Autodesk Fusion 360 part; units mm, degrees
(part 3 of 8)
  spline S51 degree 5 poles (4.880225, -3.252666) (4.880415, -3.252751) (4.882389, -3.253634) (4.886153, -3.255305) (4.891721, -3.257742) (4.899117, -3.260906) (4.908178, -3.264669) (4.917292, -3.268345) (4.926453, -3.271945) (4.935655, -3.275478) (4.944894, -3.278951) (4.954168, -3.282368) (4.963475, -3.28573) (4.972817, -3.289036) (4.982195, -3.292282) (4.991608, -3.295469) (5.001056, -3.298597) (5.010539, -3.301666) (5.020055, -3.30468) (5.029603, -3.30764) (5.03918, -3.310549) (5.048788, -3.313407) (5.058424, -3.316215) (5.068089, -3.318973) (5.077782, -3.321682) (5.087504, -3.324341) (5.097254, -3.326951) (5.107031, -3.329512) (5.116835, -3.332026) (5.126666, -3.334492) (5.136522, -3.336912) (5.146404, -3.339287) (5.156311, -3.341616) (5.166242, -3.3439) (5.176198, -3.346139) (5.186178, -3.348333) (5.196182, -3.350483) (5.20621, -3.35259) (5.216261, -3.354653) (5.226335, -3.356672) (5.236431, -3.358649) (5.24655, -3.360583) (5.256691, -3.362476) (5.266853, -3.364326) (5.277038, -3.366134) (5.287243, -3.367901) (5.29747, -3.369627) (5.307717, -3.371311) (5.317985, -3.372955) (5.328274, -3.374558) (5.338583, -3.376121) (5.348911, -3.377644) (5.35926, -3.379126) (5.369627, -3.380569) (5.380015, -3.381972) (5.390421, -3.383336) (5.400847, -3.38466) (5.411291, -3.385946) (5.421753, -3.387192) (5.432234, -3.3884) (5.442733, -3.389569) (5.45325, -3.390699) (5.463785, -3.391792) (5.472228, -3.392635) (5.478567, -3.39325) (5.482797, -3.393652) (5.484913, -3.393852) knots 0.1270499 0.1270499 0.1270499 0.1270499 0.1270499 0.1270499 0.12857143 0.14285714 0.15714286 0.17142857 0.18571429 0.2 0.21428571 0.22857143 0.24285714 0.25714286 0.27142857 0.28571429 0.3 0.31428571 0.32857143 0.34285714 0.35714286 0.37142857 0.38571429 0.4 0.41428571 0.42857143 0.44285714 0.45714286 0.47142857 0.48571429 0.5 0.51428571 0.52857143 0.54285714 0.55714286 0.57142857 0.58571429 0.6 0.61428571 0.62857143 0.64285714 0.65714286 0.67142857 0.68571429 0.7 0.71428571 0.72857143 0.74285714 0.75714286 0.77142857 0.78571429 0.8 0.81428571 0.82857143 0.84285714 0.85714286 0.87142857 0.88571429 0.9 0.91428571 0.92857143 0.94285714 0.95714286 0.97142857 0.98571429 1 1 1 1 1 1
  arc A17 (5.484913, -3.393852) -> (5.601792, -3.197253) centre (0, 0) ccw
  spline S52 degree 5 poles (5.601792, -3.197253) (5.600606, -3.19549) (5.598232, -3.191966) (5.594663, -3.18669) (5.589889, -3.179676) (5.583897, -3.170943) (5.577879, -3.162244) (5.571837, -3.153579) (5.565769, -3.144948) (5.559676, -3.136352) (5.553557, -3.127791) (5.547413, -3.119264) (5.541244, -3.110774) (5.535049, -3.102319) (5.528828, -3.0939) (5.522582, -3.085517) (5.51631, -3.07717) (5.510013, -3.068861) (5.503689, -3.060588) (5.49734, -3.052352) (5.490965, -3.044155) (5.484563, -3.035995) (5.478136, -3.027873) (5.471682, -3.01979) (5.465201, -3.011746) (5.458695, -3.003741) (5.452161, -2.995776) (5.445601, -2.98785) (5.439015, -2.979965) (5.432401, -2.972121) (5.42576, -2.964318) (5.419092, -2.956556) (5.412396, -2.948837) (5.405673, -2.94116) (5.398922, -2.933526) (5.392144, -2.925935) (5.385337, -2.918388) (5.378502, -2.910886) (5.371639, -2.903428) (5.364747, -2.896016) (5.357826, -2.88865) (5.350876, -2.881331) (5.343895, -2.874061) (5.336885, -2.866839) (5.329845, -2.859666) (5.322774, -2.852542) (5.315674, -2.845467) (5.308543, -2.838442) (5.301382, -2.831469) (5.294188, -2.824549) (5.286961, -2.817684) (5.2797, -2.810878) (5.272403, -2.804131) (5.265071, -2.797443) (5.257705, -2.790815) (5.250305, -2.784245) (5.242872, -2.77773) (5.235408, -2.771273) (5.227908, -2.764876) (5.220369, -2.758548) (5.212786, -2.752298) (5.205152, -2.746135) (5.198838, -2.741149) (5.194037, -2.737422) (5.190771, -2.734913) (5.189053, -2.7336) (5.188887, -2.733474) knots -1 -1 -1 -1 -1 -1 -0.98571429 -0.97142857 -0.95714286 -0.94285714 -0.92857143 -0.91428571 -0.9 -0.88571429 -0.87142857 -0.85714286 -0.84285714 -0.82857143 -0.81428571 -0.8 -0.78571429 -0.77142857 -0.75714286 -0.74285714 -0.72857143 -0.71428571 -0.7 -0.68571429 -0.67142857 -0.65714286 -0.64285714 -0.62857143 -0.61428571 -0.6 -0.58571429 -0.57142857 -0.55714286 -0.54285714 -0.52857143 -0.51428571 -0.5 -0.48571429 -0.47142857 -0.45714286 -0.44285714 -0.42857143 -0.41428571 -0.4 -0.38571429 -0.37142857 -0.35714286 -0.34285714 -0.32857143 -0.31428571 -0.3 -0.28571429 -0.27142857 -0.25714286 -0.24285714 -0.22857143 -0.21428571 -0.2 -0.18571429 -0.17142857 -0.15714286 -0.14285714 -0.12857143 -0.1270499 -0.1270499 -0.1270499 -0.1270499 -0.1270499 -0.1270499
  spline S53 degree 3 poles (5.319548, -2.469584) (5.300709, -2.464423) (5.281043, -2.462992) (5.242269, -2.467747) (5.223532, -2.473889) (5.189467, -2.49301) (5.174464, -2.505805) (5.150209, -2.536427) (5.141187, -2.55396) (5.130373, -2.591498) (5.128683, -2.611143) (5.13293, -2.649976) (5.138825, -2.668792) (5.153188, -2.695188) (5.159174, -2.703872) (5.172862, -2.719846) (5.180527, -2.727091) (5.188887, -2.733474) knots 0 0 0 0 0.00585967 0.00585967 0.01171933 0.01171933 0.017579 0.017579 0.02343867 0.02343867 0.02929834 0.02929834 0.035158 0.035158 0.03831344 0.03831344 0.04146887 0.04146887 0.04146887 0.04146887
  spline S54 degree 5 poles (5.319548, -2.469584) (5.319748, -2.469639) (5.321834, -2.470209) (5.325809, -2.471286) (5.331684, -2.472845) (5.339477, -2.474843) (5.349006, -2.477178) (5.358574, -2.479421) (5.368177, -2.48158) (5.377811, -2.483666) (5.387472, -2.485688) (5.397158, -2.48765) (5.40687, -2.489552) (5.416607, -2.491392) (5.42637, -2.49317) (5.436159, -2.494882) (5.445975, -2.496531) (5.455815, -2.498117) (5.465679, -2.499643) (5.475567, -2.501111) (5.485476, -2.502523) (5.495407, -2.503881) (5.505359, -2.505186) (5.515332, -2.506436) (5.525325, -2.507633) (5.535339, -2.508777) (5.545373, -2.509868) (5.555427, -2.510907) (5.565499, -2.511894) (5.575591, -2.512832) (5.585702, -2.513719) (5.59583, -2.514557) (5.605976, -2.515346) (5.61614, -2.516087) (5.626321, -2.51678) (5.636519, -2.517426) (5.646734, -2.518024) (5.656966, -2.518575) (5.667214, -2.519079) (5.677478, -2.519537) (5.687758, -2.51995) (5.698053, -2.520317) (5.708364, -2.520639) (5.71869, -2.520916) (5.729031, -2.521149) (5.739387, -2.521337) (5.749757, -2.521481) (5.760141, -2.521582) (5.77054, -2.521639) (5.780953, -2.521653) (5.791379, -2.521623) (5.801819, -2.521552) (5.812272, -2.521437) (5.822739, -2.52128) (5.833219, -2.521081) (5.843712, -2.520841) (5.854217, -2.520558) (5.864735, -2.520234) (5.875265, -2.519869) (5.885808, -2.519462) (5.896362, -2.519015) (5.906928, -2.518527) (5.917507, -2.517998) (5.925979, -2.517543) (5.932338, -2.517183) (5.93658, -2.516935) (5.938701, -2.516809) knots 0.1270499 0.1270499 0.1270499 0.1270499 0.1270499 0.1270499 0.12857143 0.14285714 0.15714286 0.17142857 0.18571429 0.2 0.21428571 0.22857143 0.24285714 0.25714286 0.27142857 0.28571429 0.3 0.31428571 0.32857143 0.34285714 0.35714286 0.37142857 0.38571429 0.4 0.41428571 0.42857143 0.44285714 0.45714286 0.47142857 0.48571429 0.5 0.51428571 0.52857143 0.54285714 0.55714286 0.57142857 0.58571429 0.6 0.61428571 0.62857143 0.64285714 0.65714286 0.67142857 0.68571429 0.7 0.71428571 0.72857143 0.74285714 0.75714286 0.77142857 0.78571429 0.8 0.81428571 0.82857143 0.84285714 0.85714286 0.87142857 0.88571429 0.9 0.91428571 0.92857143 0.94285714 0.95714286 0.97142857 0.98571429 1 1 1 1 1 1
  arc A18 (5.938701, -2.516809) -> (6.0242, -2.304673) centre (0, 0) ccw
  spline S55 degree 5 poles (6.0242, -2.304673) (6.022758, -2.303111) (6.019874, -2.299991) (6.015542, -2.295322) (6.009753, -2.289119) (6.002498, -2.281403) (5.995223, -2.273724) (5.987929, -2.266083) (5.980614, -2.25848) (5.97328, -2.250915) (5.965927, -2.243388) (5.958553, -2.235899) (5.95116, -2.22845) (5.943747, -2.22104) (5.936314, -2.213669) (5.928862, -2.206338) (5.921389, -2.199046) (5.913897, -2.191795) (5.906385, -2.184585) (5.898853, -2.177415) (5.891301, -2.170287) (5.883729, -2.1632) (5.876137, -2.156154) (5.868525, -2.149151) (5.860892, -2.14219) (5.85324, -2.135273) (5.845567, -2.128398) (5.837874, -2.121567) (5.830161, -2.114779) (5.822427, -2.108037) (5.814673, -2.101339) (5.806899, -2.094686) (5.799103, -2.088079) (5.791287, -2.081519) (5.78345, -2.075005) (5.775592, -2.068538) (5.767713, -2.062118) (5.759813, -2.055747) (5.751892, -2.049424) (5.743949, -2.043151) (5.735985, -2.036928) (5.727999, -2.030756) (5.71999, -2.024636) (5.71196, -2.018569) (5.703907, -2.012555) (5.695832, -2.006593) (5.687735, -2.000685) (5.679616, -1.994832) (5.671473, -1.989033) (5.663308, -1.983292) (5.655118, -1.977611) (5.646903, -1.971993) (5.638662, -1.966439) (5.630395, -1.960949) (5.622103, -1.955523) (5.613786, -1.950159) (5.605447, -1.944856) (5.597084, -1.939614) (5.588696, -1.934437) (5.580279, -1.929333) (5.57183, -1.924314) (5.563345, -1.919389) (5.556345, -1.915425) (5.551031, -1.912474) (5.54742, -1.910494) (5.545521, -1.909458) (5.545338, -1.909359) knots -1 -1 -1 -1 -1 -1 -0.98571429 -0.97142857 -0.95714286 -0.94285714 -0.92857143 -0.91428571 -0.9 -0.88571429 -0.87142857 -0.85714286 -0.84285714 -0.82857143 -0.81428571 -0.8 -0.78571429 -0.77142857 -0.75714286 -0.74285714 -0.72857143 -0.71428571 -0.7 -0.68571429 -0.67142857 -0.65714286 -0.64285714 -0.62857143 -0.61428571 -0.6 -0.58571429 -0.57142857 -0.55714286 -0.54285714 -0.52857143 -0.51428571 -0.5 -0.48571429 -0.47142857 -0.45714286 -0.44285714 -0.42857143 -0.41428571 -0.4 -0.38571429 -0.37142857 -0.35714286 -0.34285714 -0.32857143 -0.31428571 -0.3 -0.28571429 -0.27142857 -0.25714286 -0.24285714 -0.22857143 -0.21428571 -0.2 -0.18571429 -0.17142857 -0.15714286 -0.14285714 -0.12857143 -0.1270499 -0.1270499 -0.1270499 -0.1270499 -0.1270499 -0.1270499
  spline S56 degree 3 poles (5.634185, -1.628616) (5.61478, -1.626392) (5.595126, -1.627979) (5.557532, -1.638598) (5.539952, -1.647528) (5.509205, -1.671624) (5.496331, -1.68656) (5.477034, -1.720525) (5.470795, -1.73923) (5.465837, -1.777979) (5.467167, -1.797652) (5.477291, -1.835382) (5.48599, -1.853077) (5.504214, -1.876971) (5.511455, -1.88464) (5.527421, -1.898337) (5.536102, -1.904327) (5.545338, -1.909359) knots 0 0 0 0 0.00585967 0.00585967 0.01171933 0.01171933 0.017579 0.017579 0.02343867 0.02343867 0.02929834 0.02929834 0.035158 0.035158 0.03831344 0.03831344 0.04146887 0.04146887 0.04146887 0.04146887
  spline S57 degree 5 poles (5.634185, -1.628616) (5.634392, -1.62864) (5.63654, -1.628885) (5.640633, -1.629343) (5.646677, -1.629986) (5.654683, -1.630772) (5.664457, -1.631625) (5.674256, -1.63238) (5.684076, -1.633048) (5.693915, -1.63364) (5.703771, -1.634163) (5.713644, -1.634624) (5.723532, -1.635021) (5.733436, -1.635353) (5.743356, -1.635619) (5.753292, -1.635818) (5.763244, -1.635948) (5.773211, -1.636014) (5.783193, -1.636016) (5.793188, -1.635957) (5.803197, -1.635841) (5.813219, -1.635667) (5.823253, -1.635437) (5.8333, -1.63515) (5.843359, -1.634808) (5.85343, -1.63441) (5.863513, -1.633956) (5.873607, -1.633448) (5.883713, -1.632887) (5.89383, -1.632272) (5.903957, -1.631606) (5.914094, -1.630888) (5.924242, -1.630119) (5.9344, -1.6293) (5.944568, -1.628431) (5.954745, -1.627512) (5.964931, -1.626544) (5.975127, -1.625526) (5.985332, -1.62446) (5.995546, -1.623346) (6.005768, -1.622185) (6.015999, -1.620976) (6.026238, -1.61972) (6.036485, -1.618418) (6.046741, -1.617069) (6.057004, -1.615675) (6.067274, -1.614234) (6.077553, -1.612748) (6.087838, -1.611217) (6.098131, -1.609642) (6.108431, -1.608021) (6.118737, -1.606357) (6.129051, -1.604648) (6.139371, -1.602895) (6.149697, -1.601099) (6.16003, -1.599259) (6.170369, -1.597376) (6.180715, -1.595451) (6.191066, -1.593482) (6.201423, -1.591471) (6.211785, -1.589418) (6.222153, -1.587323) (6.232527, -1.585185) (6.24083, -1.583442) (6.24706, -1.582116) (6.251214, -1.581223) (6.253291, -1.580775) knots 0.1270499 0.1270499 0.1270499 0.1270499 0.1270499 0.1270499 0.12857143 0.14285714 0.15714286 0.17142857 0.18571429 0.2 0.21428571 0.22857143 0.24285714 0.25714286 0.27142857 0.28571429 0.3 0.31428571 0.32857143 0.34285714 0.35714286 0.37142857 0.38571429 0.4 0.41428571 0.42857143 0.44285714 0.45714286 0.47142857 0.48571429 0.5 0.51428571 0.52857143 0.54285714 0.55714286 0.57142857 0.58571429 0.6 0.61428571 0.62857143 0.64285714 0.65714286 0.67142857 0.68571429 0.7 0.71428571 0.72857143 0.74285714 0.75714286 0.77142857 0.78571429 0.8 0.81428571 0.82857143 0.84285714 0.85714286 0.87142857 0.88571429 0.9 0.91428571 0.92857143 0.94285714 0.95714286 0.97142857 0.98571429 1 1 1 1 1 1
  arc A19 (6.253291, -1.580775) -> (6.305405, -1.358074) centre (0, 0) ccw
  spline S58 degree 5 poles (6.305405, -1.358074) (6.303743, -1.35675) (6.300416, -1.354107) (6.295421, -1.350154) (6.288754, -1.344907) (6.280406, -1.338389) (6.272044, -1.331911) (6.263669, -1.325473) (6.255279, -1.319075) (6.246877, -1.312718) (6.23846, -1.306402) (6.23003, -1.300127) (6.221586, -1.293893) (6.213129, -1.287701) (6.204658, -1.281551) (6.196174, -1.275444) (6.187676, -1.269379) (6.179165, -1.263356) (6.17064, -1.257377) (6.162102, -1.251441) (6.15355, -1.245549) (6.144985, -1.239701) (6.136406, -1.233897) (6.127814, -1.228138) (6.119209, -1.222424) (6.11059, -1.216755) (6.101958, -1.211132) (6.093313, -1.205555) (6.084654, -1.200025) (6.075981, -1.194542) (6.067296, -1.189106) (6.058596, -1.183718) (6.049884, -1.178379) (6.041158, -1.173088) (6.032418, -1.167847) (6.023665, -1.162655) (6.014899, -1.157514) (6.006119, -1.152423) (5.997325, -1.147383) (5.988518, -1.142396) (5.979697, -1.137462) (5.970863, -1.132581) (5.962014, -1.127756) (5.953151, -1.122985) (5.944275, -1.118271) (5.935384, -1.113612) (5.92648, -1.10901) (5.917562, -1.104464) (5.908631, -1.099976) (5.899684, -1.095549) (5.890723, -1.091185) (5.881747, -1.086886) (5.872754, -1.082655) (5.863746, -1.078492) (5.854723, -1.074396) (5.845686, -1.070364) (5.836634, -1.066395) (5.827569, -1.062491) (5.818489, -1.058656) (5.809392, -1.054897) (5.800276, -1.051226) (5.791138, -1.047654) (5.783615, -1.044805) (5.777913, -1.0427) (5.774042, -1.041294) (5.772007, -1.040561) (5.771812, -1.04049) knots -1 -1 -1 -1 -1 -1 -0.98571429 -0.97142857 -0.95714286 -0.94285714 -0.92857143 -0.91428571 -0.9 -0.88571429 -0.87142857 -0.85714286 -0.84285714 -0.82857143 -0.81428571 -0.8 -0.78571429 -0.77142857 -0.75714286 -0.74285714 -0.72857143 -0.71428571 -0.7 -0.68571429 -0.67142857 -0.65714286 -0.64285714 -0.62857143 -0.61428571 -0.6 -0.58571429 -0.57142857 -0.55714286 -0.54285714 -0.52857143 -0.51428571 -0.5 -0.48571429 -0.47142857 -0.45714286 -0.44285714 -0.42857143 -0.41428571 -0.4 -0.38571429 -0.37142857 -0.35714286 -0.34285714 -0.32857143 -0.31428571 -0.3 -0.28571429 -0.27142857 -0.25714286 -0.24285714 -0.22857143 -0.21428571 -0.2 -0.18571429 -0.17142857 -0.15714286 -0.14285714 -0.12857143 -0.1270499 -0.1270499 -0.1270499 -0.1270499 -0.1270499 -0.1270499
  spline S59 degree 3 poles (5.816762, -0.749475) (5.797244, -0.750239) (5.778063, -0.754808) (5.742531, -0.771041) (5.72652, -0.78255) (5.699811, -0.811057) (5.689369, -0.827783) (5.675482, -0.864296) (5.672172, -0.883734) (5.673187, -0.922786) (5.677504, -0.942025) (5.693269, -0.977767) (5.704567, -0.993928) (5.726225, -1.014759) (5.734552, -1.021233) (5.752422, -1.032332) (5.761915, -1.036927) (5.771812, -1.04049) knots 0 0 0 0 0.00585967 0.00585967 0.01171933 0.01171933 0.017579 0.017579 0.02343867 0.02343867 0.02929834 0.02929834 0.035158 0.035158 0.03831344 0.03831344 0.04146887 0.04146887 0.04146887 0.04146887
  spline S60 degree 5 poles (5.816762, -0.749475) (5.81697, -0.749467) (5.81913, -0.749382) (5.823245, -0.749209) (5.829317, -0.748922) (5.837349, -0.748477) (5.847139, -0.747827) (5.856937, -0.747078) (5.866744, -0.74624) (5.876559, -0.745322) (5.886379, -0.744335) (5.896206, -0.743283) (5.906039, -0.742166) (5.915878, -0.740983) (5.925722, -0.739731) (5.935572, -0.738411) (5.945427, -0.737021) (5.955288, -0.735564) (5.965153, -0.734042) (5.975022, -0.732459) (5.984896, -0.730815) (5.994774, -0.729114) (6.004655, -0.727355) (6.014541, -0.725538) (6.02443, -0.723664) (6.034322, -0.721733) (6.044217, -0.719746) (6.054116, -0.717703) (6.064017, -0.715605) (6.073922, -0.713454) (6.083828, -0.711249) (6.093738, -0.708992) (6.103649, -0.706684) (6.113563, -0.704324) (6.123479, -0.701913) (6.133396, -0.699451) (6.143316, -0.696939) (6.153237, -0.694377) (6.163159, -0.691766) (6.173083, -0.689106) (6.183008, -0.686397) (6.192935, -0.683641) (6.202862, -0.680837) (6.212791, -0.677986) (6.22272, -0.675087) (6.23265, -0.672142) (6.24258, -0.669151) (6.252511, -0.666114) (6.262442, -0.66303) (6.272374, -0.659902) (6.282306, -0.656728) (6.292237, -0.65351) (6.302169, -0.650247) (6.312101, -0.646939) (6.322032, -0.643588) (6.331963, -0.640192) (6.341894, -0.636753) (6.351824, -0.633271) (6.361753, -0.629745) (6.371681, -0.626177) (6.381609, -0.622566) (6.391536, -0.618913) (6.401461, -0.615217) (6.409401, -0.612226) (6.415355, -0.609965) (6.419325, -0.608448) (6.421309, -0.607688) knots 0.1270499 0.1270499 0.1270499 0.1270499 0.1270499 0.1270499 0.12857143 0.14285714 0.15714286 0.17142857 0.18571429 0.2 0.21428571 0.22857143 0.24285714 0.25714286 0.27142857 0.28571429 0.3 0.31428571 0.32857143 0.34285714 0.35714286 0.37142857 0.38571429 0.4 0.41428571 0.42857143 0.44285714 0.45714286 0.47142857 0.48571429 0.5 0.51428571 0.52857143 0.54285714 0.55714286 0.57142857 0.58571429 0.6 0.61428571 0.62857143 0.64285714 0.65714286 0.67142857 0.68571429 0.7 0.71428571 0.72857143 0.74285714 0.75714286 0.77142857 0.78571429 0.8 0.81428571 0.82857143 0.84285714 0.85714286 0.87142857 0.88571429 0.9 0.91428571 0.92857143 0.94285714 0.95714286 0.97142857 0.98571429 1 1 1 1 1 1
  arc A20 (6.421309, -0.607688) -> (6.438818, -0.379642) centre (0, 0) ccw
  spline S61 degree 5 poles (6.438818, -0.379642) (6.436972, -0.378588) (6.433281, -0.376483) (6.427742, -0.373339) (6.420351, -0.369172) (6.411106, -0.364004) (6.401854, -0.358878) (6.392594, -0.353794) (6.383326, -0.348752) (6.374051, -0.343752) (6.364769, -0.338795) (6.35548, -0.33388) (6.346184, -0.329009) (6.33688, -0.32418) (6.32757, -0.319395) (6.318253, -0.314655) (6.308929, -0.309958) (6.299598, -0.305305) (6.29026, -0.300697) (6.280916, -0.296134) (6.271565, -0.291617) (6.262208, -0.287144) (6.252844, -0.282718) (6.243473, -0.278338) (6.234097, -0.274005) (6.224714, -0.269718) (6.215324, -0.265479) (6.205929, -0.261287) (6.196527, -0.257143) (6.187119, -0.253048) (6.177706, -0.249002) (6.168286, -0.245005) (6.15886, -0.241058) (6.149429, -0.237162) (6.139992, -0.233316) (6.130549, -0.229521) (6.1211, -0.225778) (6.111646, -0.222087) (6.102186, -0.218449) (6.092721, -0.214865) (6.08325, -0.211335) (6.073774, -0.20786) (6.064293, -0.204442) (6.054806, -0.20108) (6.045314, -0.197776) (6.035816, -0.194529) (6.026314, -0.19134) (6.016807, -0.188208) (6.007295, -0.185137) (5.997777, -0.182127) (5.988255, -0.179182) (5.978728, -0.176304) (5.969195, -0.173495) (5.959657, -0.170756) (5.950114, -0.168085) (5.940567, -0.16548) (5.931016, -0.16294) (5.921461, -0.160465) (5.911902, -0.15806) (5.902338, -0.155734) (5.892768, -0.153498) (5.883192, -0.151362) (5.875322, -0.149696) (5.869366, -0.148486) (5.865325, -0.147687) (5.863203, -0.147273) (5.862998, -0.147233) knots -1 -1 -1 -1 -1 -1 -0.98571429 -0.97142857 -0.95714286 -0.94285714 -0.92857143 -0.91428571 -0.9 -0.88571429 -0.87142857 -0.85714286 -0.84285714 -0.82857143 -0.81428571 -0.8 -0.78571429 -0.77142857 -0.75714286 -0.74285714 -0.72857143 -0.71428571 -0.7 -0.68571429 -0.67142857 -0.65714286 -0.64285714 -0.62857143 -0.61428571 -0.6 -0.58571429 -0.57142857 -0.55714286 -0.54285714 -0.52857143 -0.51428571 -0.5 -0.48571429 -0.47142857 -0.45714286 -0.44285714 -0.42857143 -0.41428571 -0.4 -0.38571429 -0.37142857 -0.35714286 -0.34285714 -0.32857143 -0.31428571 -0.3 -0.28571429 -0.27142857 -0.25714286 -0.24285714 -0.22857143 -0.21428571 -0.2 -0.18571429 -0.17142857 -0.15714286 -0.14285714 -0.12857143 -0.1270499 -0.1270499 -0.1270499 -0.1270499 -0.1270499 -0.1270499
  spline S62 degree 3 poles (5.862998, 0.147233) (5.843827, 0.143499) (5.825567, 0.136055) (5.79293, 0.114589) (5.778863, 0.10077) (5.756819, 0.06852) (5.749052, 0.050396) (5.740902, 0.012191) (5.740598, -0.007524) (5.747562, -0.045963) (5.754765, -0.064318) (5.775802, -0.097235) (5.789434, -0.111481) (5.814018, -0.128763) (5.823236, -0.13389) (5.84259, -0.142131) (5.852674, -0.145222) (5.862998, -0.147233) knots 0 0 0 0 0.00585967 0.00585967 0.01171933 0.01171933 0.017579 0.017579 0.02343867 0.02343867 0.02929834 0.02929834 0.035158 0.035158 0.03831344 0.03831344 0.04146887 0.04146887 0.04146887 0.04146887
  spline S63 degree 5 poles (5.862998, 0.147233) (5.863203, 0.147273) (5.865325, 0.147687) (5.869366, 0.148486) (5.875322, 0.149696) (5.883192, 0.151362) (5.892768, 0.153498) (5.902338, 0.155734) (5.911902, 0.15806) (5.921461, 0.160465) (5.931016, 0.16294) (5.940567, 0.16548) (5.950114, 0.168085) (5.959657, 0.170756) (5.969195, 0.173495) (5.978728, 0.176304) (5.988255, 0.179182) (5.997777, 0.182127) (6.007295, 0.185137) (6.016807, 0.188208) (6.026314, 0.19134) (6.035816, 0.194529) (6.045314, 0.197776) (6.054806, 0.20108) (6.064293, 0.204442) (6.073774, 0.20786) (6.08325, 0.211335) (6.092721, 0.214865) (6.102186, 0.218449) (6.111646, 0.222087) (6.1211, 0.225778) (6.130549, 0.229521) (6.139992, 0.233316) (6.149429, 0.237162) (6.15886, 0.241058) (6.168286, 0.245005) (6.177706, 0.249002) (6.187119, 0.253048) (6.196527, 0.257143) (6.205929, 0.261287) (6.215324, 0.265479) (6.224714, 0.269718) (6.234097, 0.274005) (6.243473, 0.278338) (6.252844, 0.282718) (6.262208, 0.287144) (6.271565, 0.291617) (6.280916, 0.296134) (6.29026, 0.300697) (6.299598, 0.305305) (6.308929, 0.309958) (6.318253, 0.314655) (6.32757, 0.319395) (6.33688, 0.32418) (6.346184, 0.329009) (6.35548, 0.33388) (6.364769, 0.338795) (6.374051, 0.343752) (6.383326, 0.348752) (6.392594, 0.353794) (6.401854, 0.358878) (6.411106, 0.364004) (6.420351, 0.369172) (6.427742, 0.373339) (6.433281, 0.376483) (6.436972, 0.378588) (6.438818, 0.379642) knots 0.1270499 0.1270499 0.1270499 0.1270499 0.1270499 0.1270499 0.12857143 0.14285714 0.15714286 0.17142857 0.18571429 0.2 0.21428571 0.22857143 0.24285714 0.25714286 0.27142857 0.28571429 0.3 0.31428571 0.32857143 0.34285714 0.35714286 0.37142857 0.38571429 0.4 0.41428571 0.42857143 0.44285714 0.45714286 0.47142857 0.48571429 0.5 0.51428571 0.52857143 0.54285714 0.55714286 0.57142857 0.58571429 0.6 0.61428571 0.62857143 0.64285714 0.65714286 0.67142857 0.68571429 0.7 0.71428571 0.72857143 0.74285714 0.75714286 0.77142857 0.78571429 0.8 0.81428571 0.82857143 0.84285714 0.85714286 0.87142857 0.88571429 0.9 0.91428571 0.92857143 0.94285714 0.95714286 0.97142857 0.98571429 1 1 1 1 1 1
  arc A21 (6.438818, 0.379642) -> (6.421309, 0.607688) centre (0, 0) ccw
  spline S64 degree 5 poles (6.421309, 0.607688) (6.419325, 0.608448) (6.415355, 0.609965) (6.409401, 0.612226) (6.401461, 0.615217) (6.391536, 0.618913) (6.381609, 0.622566) (6.371681, 0.626177) (6.361753, 0.629745) (6.351824, 0.633271) (6.341894, 0.636753) (6.331963, 0.640192) (6.322032, 0.643588) (6.312101, 0.646939) (6.302169, 0.650247) (6.292237, 0.65351) (6.282306, 0.656728) (6.272374, 0.659902) (6.262442, 0.66303) (6.252511, 0.666114) (6.24258, 0.669151) (6.23265, 0.672142) (6.22272, 0.675087) (6.212791, 0.677986) (6.202862, 0.680837) (6.192935, 0.683641) (6.183008, 0.686397) (6.173083, 0.689106) (6.163159, 0.691766) (6.153237, 0.694377) (6.143316, 0.696939) (6.133396, 0.699451) (6.123479, 0.701913) (6.113563, 0.704324) (6.103649, 0.706684) (6.093738, 0.708992) (6.083828, 0.711249) (6.073922, 0.713454) (6.064017, 0.715605) (6.054116, 0.717703) (6.044217, 0.719746) (6.034322, 0.721733) (6.02443, 0.723664) (6.014541, 0.725538) (6.004655, 0.727355) (5.994774, 0.729114) (5.984896, 0.730815) (5.975022, 0.732459) (5.965153, 0.734042) (5.955288, 0.735564) (5.945427, 0.737021) (5.935572, 0.738411) (5.925722, 0.739731) (5.915878, 0.740983) (5.906039, 0.742166) (5.896206, 0.743283) (5.886379, 0.744335) (5.876559, 0.745322) (5.866744, 0.74624) (5.856937, 0.747078) (5.847139, 0.747827) (5.837349, 0.748477) (5.829317, 0.748922) (5.823245, 0.749209) (5.81913, 0.749382) (5.81697, 0.749467) (5.816762, 0.749475) knots -1 -1 -1 -1 -1 -1 -0.98571429 -0.97142857 -0.95714286 -0.94285714 -0.92857143 -0.91428571 -0.9 -0.88571429 -0.87142857 -0.85714286 -0.84285714 -0.82857143 -0.81428571 -0.8 -0.78571429 -0.77142857 -0.75714286 -0.74285714 -0.72857143 -0.71428571 -0.7 -0.68571429 -0.67142857 -0.65714286 -0.64285714 -0.62857143 -0.61428571 -0.6 -0.58571429 -0.57142857 -0.55714286 -0.54285714 -0.52857143 -0.51428571 -0.5 -0.48571429 -0.47142857 -0.45714286 -0.44285714 -0.42857143 -0.41428571 -0.4 -0.38571429 -0.37142857 -0.35714286 -0.34285714 -0.32857143 -0.31428571 -0.3 -0.28571429 -0.27142857 -0.25714286 -0.24285714 -0.22857143 -0.21428571 -0.2 -0.18571429 -0.17142857 -0.15714286 -0.14285714 -0.12857143 -0.1270499 -0.1270499 -0.1270499 -0.1270499 -0.1270499 -0.1270499
  spline S65 degree 3 poles (5.771812, 1.04049) (5.753434, 1.033873) (5.736525, 1.02373) (5.707547, 0.997532) (5.695755, 0.981729) (5.678892, 0.946491) (5.673983, 0.927394) (5.67176, 0.888393) (5.674469, 0.868862) (5.68722, 0.831937) (5.69714, 0.814896) (5.722955, 0.785577) (5.738602, 0.773578) (5.765536, 0.760252) (5.775428, 0.756592) (5.795814, 0.751402) (5.806252, 0.749886) (5.816762, 0.749475) knots 0 0 0 0 0.00585967 0.00585967 0.01171933 0.01171933 0.017579 0.017579 0.02343867 0.02343867 0.02929834 0.02929834 0.035158 0.035158 0.03831344 0.03831344 0.04146887 0.04146887 0.04146887 0.04146887
  spline S66 degree 5 poles (5.771812, 1.04049) (5.772007, 1.040561) (5.774042, 1.041294) (5.777913, 1.0427) (5.783615, 1.044805) (5.791138, 1.047654) (5.800276, 1.051226) (5.809392, 1.054897) (5.818489, 1.058656) (5.827569, 1.062491) (5.836634, 1.066395) (5.845686, 1.070364) (5.854723, 1.074396) (5.863746, 1.078492) (5.872754, 1.082655) (5.881747, 1.086886) (5.890723, 1.091185) (5.899684, 1.095549) (5.908631, 1.099976) (5.917562, 1.104464) (5.92648, 1.10901) (5.935384, 1.113612) (5.944275, 1.118271) (5.953151, 1.122985) (5.962014, 1.127756) (5.970863, 1.132581) (5.979697, 1.137462) (5.988518, 1.142396) (5.997325, 1.147383) (6.006119, 1.152423) (6.014899, 1.157514) (6.023665, 1.162655) (6.032418, 1.167847) (6.041158, 1.173088) (6.049884, 1.178379) (6.058596, 1.183718) (6.067296, 1.189106) (6.075981, 1.194542) (6.084654, 1.200025) (6.093313, 1.205555) (6.101958, 1.211132) (6.11059, 1.216755) (6.119209, 1.222424) (6.127814, 1.228138) (6.136406, 1.233897) (6.144985, 1.239701) (6.15355, 1.245549) (6.162102, 1.251441) (6.17064, 1.257377) (6.179165, 1.263356) (6.187676, 1.269379) (6.196174, 1.275444) (6.204658, 1.281551) (6.213129, 1.287701) (6.221586, 1.293893) (6.23003, 1.300127) (6.23846, 1.306402) (6.246877, 1.312718) (6.255279, 1.319075) (6.263669, 1.325473) (6.272044, 1.331911) (6.280406, 1.338389) (6.288754, 1.344907) (6.295421, 1.350154) (6.300416, 1.354107) (6.303743, 1.35675) (6.305405, 1.358074) knots 0.1270499 0.1270499 0.1270499 0.1270499 0.1270499 0.1270499 0.12857143 0.14285714 0.15714286 0.17142857 0.18571429 0.2 0.21428571 0.22857143 0.24285714 0.25714286 0.27142857 0.28571429 0.3 0.31428571 0.32857143 0.34285714 0.35714286 0.37142857 0.38571429 0.4 0.41428571 0.42857143 0.44285714 0.45714286 0.47142857 0.48571429 0.5 0.51428571 0.52857143 0.54285714 0.55714286 0.57142857 0.58571429 0.6 0.61428571 0.62857143 0.64285714 0.65714286 0.67142857 0.68571429 0.7 0.71428571 0.72857143 0.74285714 0.75714286 0.77142857 0.78571429 0.8 0.81428571 0.82857143 0.84285714 0.85714286 0.87142857 0.88571429 0.9 0.91428571 0.92857143 0.94285714 0.95714286 0.97142857 0.98571429 1 1 1 1 1 1
  arc A22 (6.305405, 1.358074) -> (6.253291, 1.580775) centre (0, 0) ccw
  spline S67 degree 5 poles (6.253291, 1.580775) (6.251214, 1.581223) (6.24706, 1.582116) (6.24083, 1.583442) (6.232527, 1.585185) (6.222153, 1.587323) (6.211785, 1.589418) (6.201423, 1.591471) (6.191066, 1.593482) (6.180715, 1.595451) (6.170369, 1.597376) (6.16003, 1.599259) (6.149697, 1.601099) (6.139371, 1.602895) (6.129051, 1.604648) (6.118737, 1.606357) (6.108431, 1.608021) (6.098131, 1.609642) (6.087838, 1.611217) (6.077553, 1.612748) (6.067274, 1.614234) (6.057004, 1.615675) (6.046741, 1.617069) (6.036485, 1.618418) (6.026238, 1.61972) (6.015999, 1.620976) (6.005768, 1.622185) (5.995546, 1.623346) (5.985332, 1.62446) (5.975127, 1.625526) (5.964931, 1.626544) (5.954745, 1.627512) (5.944568, 1.628431) (5.9344, 1.6293) (5.924242, 1.630119) (5.914094, 1.630888) (5.903957, 1.631606) (5.89383, 1.632272) (5.883713, 1.632887) (5.873607, 1.633448) (5.863513, 1.633956) (5.85343, 1.63441) (5.843359, 1.634808) (5.8333, 1.63515) (5.823253, 1.635437) (5.813219, 1.635667) (5.803197, 1.635841) (5.793188, 1.635957) (5.783193, 1.636016) (5.773211, 1.636014) (5.763244, 1.635948) (5.753292, 1.635818) (5.743356, 1.635619) (5.733436, 1.635353) (5.723532, 1.635021) (5.713644, 1.634624) (5.703771, 1.634163) (5.693915, 1.63364) (5.684076, 1.633048) (5.674256, 1.63238) (5.664457, 1.631625) (5.654683, 1.630772) (5.646677, 1.629986) (5.640633, 1.629343) (5.63654, 1.628885) (5.634392, 1.62864) (5.634185, 1.628616) knots -1 -1 -1 -1 -1 -1 -0.98571429 -0.97142857 -0.95714286 -0.94285714 -0.92857143 -0.91428571 -0.9 -0.88571429 -0.87142857 -0.85714286 -0.84285714 -0.82857143 -0.81428571 -0.8 -0.78571429 -0.77142857 -0.75714286 -0.74285714 -0.72857143 -0.71428571 -0.7 -0.68571429 -0.67142857 -0.65714286 -0.64285714 -0.62857143 -0.61428571 -0.6 -0.58571429 -0.57142857 -0.55714286 -0.54285714 -0.52857143 -0.51428571 -0.5 -0.48571429 -0.47142857 -0.45714286 -0.44285714 -0.42857143 -0.41428571 -0.4 -0.38571429 -0.37142857 -0.35714286 -0.34285714 -0.32857143 -0.31428571 -0.3 -0.28571429 -0.27142857 -0.25714286 -0.24285714 -0.22857143 -0.21428571 -0.2 -0.18571429 -0.17142857 -0.15714286 -0.14285714 -0.12857143 -0.1270499 -0.1270499 -0.1270499 -0.1270499 -0.1270499 -0.1270499
  spline S68 degree 3 poles (5.545338, 1.909359) (5.528187, 1.900014) (5.513024, 1.887408) (5.488385, 1.857095) (5.479143, 1.839676) (5.467857, 1.802278) (5.46592, 1.782655) (5.469677, 1.743772) (5.475335, 1.724883) (5.493573, 1.690337) (5.505979, 1.675011) (5.535967, 1.649975) (5.553262, 1.640506) (5.581915, 1.631447) (5.592249, 1.62934) (5.613188, 1.627323) (5.623735, 1.627418) (5.634185, 1.628616) knots 0 0 0 0 0.00585967 0.00585967 0.01171933 0.01171933 0.017579 0.017579 0.02343867 0.02343867 0.02929834 0.02929834 0.035158 0.035158 0.03831344 0.03831344 0.04146887 0.04146887 0.04146887 0.04146887
  spline S69 degree 5 poles (5.545338, 1.909359) (5.545521, 1.909458) (5.54742, 1.910494) (5.551031, 1.912474) (5.556345, 1.915425) (5.563345, 1.919389) (5.57183, 1.924314) (5.580279, 1.929333) (5.588696, 1.934437) (5.597084, 1.939614) (5.605447, 1.944856) (5.613786, 1.950159) (5.622103, 1.955523) (5.630395, 1.960949) (5.638662, 1.966439) (5.646903, 1.971993) (5.655118, 1.977611) (5.663308, 1.983292) (5.671473, 1.989033) (5.679616, 1.994832) (5.687735, 2.000685) (5.695832, 2.006593) (5.703907, 2.012555) (5.71196, 2.018569) (5.71999, 2.024636) (5.727999, 2.030756) (5.735985, 2.036928) (5.743949, 2.043151) (5.751892, 2.049424) (5.759813, 2.055747) (5.767713, 2.062118) (5.775592, 2.068538) (5.78345, 2.075005) (5.791287, 2.081519) (5.799103, 2.088079) (5.806899, 2.094686) (5.814673, 2.101339) (5.822427, 2.108037) (5.830161, 2.114779) (5.837874, 2.121567) (5.845567, 2.128398) (5.85324, 2.135273) (5.860892, 2.14219) (5.868525, 2.149151) (5.876137, 2.156154) (5.883729, 2.1632) (5.891301, 2.170287) (5.898853, 2.177415) (5.906385, 2.184585) (5.913897, 2.191795) (5.921389, 2.199046) (5.928862, 2.206338) (5.936314, 2.213669) (5.943747, 2.22104) (5.95116, 2.22845) (5.958553, 2.235899) (5.965927, 2.243388) (5.97328, 2.250915) (5.980614, 2.25848) (5.987929, 2.266083) (5.995223, 2.273724) (6.002498, 2.281403) (6.009753, 2.289119) (6.015542, 2.295322) (6.019874, 2.299991) (6.022758, 2.303111) (6.0242, 2.304673) knots 0.1270499 0.1270499 0.1270499 0.1270499 0.1270499 0.1270499 0.12857143 0.14285714 0.15714286 0.17142857 0.18571429 0.2 0.21428571 0.22857143 0.24285714 0.25714286 0.27142857 0.28571429 0.3 0.31428571 0.32857143 0.34285714 0.35714286 0.37142857 0.38571429 0.4 0.41428571 0.42857143 0.44285714 0.45714286 0.47142857 0.48571429 0.5 0.51428571 0.52857143 0.54285714 0.55714286 0.57142857 0.58571429 0.6 0.61428571 0.62857143 0.64285714 0.65714286 0.67142857 0.68571429 0.7 0.71428571 0.72857143 0.74285714 0.75714286 0.77142857 0.78571429 0.8 0.81428571 0.82857143 0.84285714 0.85714286 0.87142857 0.88571429 0.9 0.91428571 0.92857143 0.94285714 0.95714286 0.97142857 0.98571429 1 1 1 1 1 1
  arc A23 (6.0242, 2.304673) -> (5.938701, 2.516809) centre (0, 0) ccw
  spline S70 degree 5 poles (5.938701, 2.516809) (5.93658, 2.516935) (5.932338, 2.517183) (5.925979, 2.517543) (5.917507, 2.517998) (5.906928, 2.518527) (5.896362, 2.519015) (5.885808, 2.519462) (5.875265, 2.519869) (5.864735, 2.520234) (5.854217, 2.520558) (5.843712, 2.520841) (5.833219, 2.521081) (5.822739, 2.52128) (5.812272, 2.521437) (5.801819, 2.521552) (5.791379, 2.521623) (5.780953, 2.521653) (5.77054, 2.521639) (5.760141, 2.521582) (5.749757, 2.521481) (5.739387, 2.521337) (5.729031, 2.521149) (5.71869, 2.520916) (5.708364, 2.520639) (5.698053, 2.520317) (5.687758, 2.51995) (5.677478, 2.519537) (5.667214, 2.519079) (5.656966, 2.518575) (5.646734, 2.518024) (5.636519, 2.517426) (5.626321, 2.51678) (5.61614, 2.516087) (5.605976, 2.515346) (5.59583, 2.514557) (5.585702, 2.513719) (5.575591, 2.512832) (5.565499, 2.511894) (5.555427, 2.510907) (5.545373, 2.509868) (5.535339, 2.508777) (5.525325, 2.507633) (5.515332, 2.506436) (5.505359, 2.505186) (5.495407, 2.503881) (5.485476, 2.502523) (5.475567, 2.501111) (5.465679, 2.499643) (5.455815, 2.498117) (5.445975, 2.496531) (5.436159, 2.494882) (5.42637, 2.49317) (5.416607, 2.491392) (5.40687, 2.489552) (5.397158, 2.48765) (5.387472, 2.485688) (5.377811, 2.483666) (5.368177, 2.48158) (5.358574, 2.479421) (5.349006, 2.477178) (5.339477, 2.474843) (5.331684, 2.472845) (5.325809, 2.471286) (5.321834, 2.470209) (5.319748, 2.469639) (5.319548, 2.469584) knots -1 -1 -1 -1 -1 -1 -0.98571429 -0.97142857 -0.95714286 -0.94285714 -0.92857143 -0.91428571 -0.9 -0.88571429 -0.87142857 -0.85714286 -0.84285714 -0.82857143 -0.81428571 -0.8 -0.78571429 -0.77142857 -0.75714286 -0.74285714 -0.72857143 -0.71428571 -0.7 -0.68571429 -0.67142857 -0.65714286 -0.64285714 -0.62857143 -0.61428571 -0.6 -0.58571429 -0.57142857 -0.55714286 -0.54285714 -0.52857143 -0.51428571 -0.5 -0.48571429 -0.47142857 -0.45714286 -0.44285714 -0.42857143 -0.41428571 -0.4 -0.38571429 -0.37142857 -0.35714286 -0.34285714 -0.32857143 -0.31428571 -0.3 -0.28571429 -0.27142857 -0.25714286 -0.24285714 -0.22857143 -0.21428571 -0.2 -0.18571429 -0.17142857 -0.15714286 -0.14285714 -0.12857143 -0.1270499 -0.1270499 -0.1270499 -0.1270499 -0.1270499 -0.1270499
  spline S71 degree 3 poles (5.188887, 2.733474) (5.173363, 2.72162) (5.160302, 2.706848) (5.140579, 2.673128) (5.134105, 2.654503) (5.128659, 2.61582) (5.129741, 2.596132) (5.139389, 2.558278) (5.147865, 2.540474) (5.171162, 2.509117) (5.185762, 2.495864) (5.21922, 2.4757) (5.237758, 2.468981) (5.267458, 2.464403) (5.277993, 2.463898) (5.298995, 2.465101) (5.309403, 2.466805) (5.319548, 2.469584) knots 0 0 0 0 0.00585967 0.00585967 0.01171933 0.01171933 0.017579 0.017579 0.02343867 0.02343867 0.02929834 0.02929834 0.035158 0.035158 0.03831344 0.03831344 0.04146887 0.04146887 0.04146887 0.04146887
  spline S72 degree 5 poles (5.188887, 2.733474) (5.189053, 2.7336) (5.190771, 2.734913) (5.194037, 2.737422) (5.198838, 2.741149) (5.205152, 2.746135) (5.212786, 2.752298) (5.220369, 2.758548) (5.227908, 2.764876) (5.235408, 2.771273) (5.242872, 2.77773) (5.250305, 2.784245) (5.257705, 2.790815) (5.265071, 2.797443) (5.272403, 2.804131) (5.2797, 2.810878) (5.286961, 2.817684) (5.294188, 2.824549) (5.301382, 2.831469) (5.308543, 2.838442) (5.315674, 2.845467) (5.322774, 2.852542) (5.329845, 2.859666) (5.336885, 2.866839) (5.343895, 2.874061) (5.350876, 2.881331) (5.357826, 2.88865) (5.364747, 2.896016) (5.371639, 2.903428) (5.378502, 2.910886) (5.385337, 2.918388) (5.392144, 2.925935) (5.398922, 2.933526) (5.405673, 2.94116) (5.412396, 2.948837) (5.419092, 2.956556) (5.42576, 2.964318) (5.432401, 2.972121) (5.439015, 2.979965) (5.445601, 2.98785) (5.452161, 2.995776) (5.458695, 3.003741) (5.465201, 3.011746) (5.471682, 3.01979) (5.478136, 3.027873) (5.484563, 3.035995) (5.490965, 3.044155) (5.49734, 3.052352) (5.503689, 3.060588) (5.510013, 3.068861) (5.51631, 3.07717) (5.522582, 3.085517) (5.528828, 3.0939) (5.535049, 3.102319) (5.541244, 3.110774) (5.547413, 3.119264) (5.553557, 3.127791) (5.559676, 3.136352) (5.565769, 3.144948) (5.571837, 3.153579) (5.577879, 3.162244) (5.583897, 3.170943) (5.589889, 3.179676) (5.594663, 3.18669) (5.598232, 3.191966) (5.600606, 3.19549) (5.601792, 3.197253) knots 0.1270499 0.1270499 0.1270499 0.1270499 0.1270499 0.1270499 0.12857143 0.14285714 0.15714286 0.17142857 0.18571429 0.2 0.21428571 0.22857143 0.24285714 0.25714286 0.27142857 0.28571429 0.3 0.31428571 0.32857143 0.34285714 0.35714286 0.37142857 0.38571429 0.4 0.41428571 0.42857143 0.44285714 0.45714286 0.47142857 0.48571429 0.5 0.51428571 0.52857143 0.54285714 0.55714286 0.57142857 0.58571429 0.6 0.61428571 0.62857143 0.64285714 0.65714286 0.67142857 0.68571429 0.7 0.71428571 0.72857143 0.74285714 0.75714286 0.77142857 0.78571429 0.8 0.81428571 0.82857143 0.84285714 0.85714286 0.87142857 0.88571429 0.9 0.91428571 0.92857143 0.94285714 0.95714286 0.97142857 0.98571429 1 1 1 1 1 1
  arc A24 (5.601792, 3.197253) -> (5.484913, 3.393852) centre (0, 0) ccw
  spline S73 degree 5 poles (5.484913, 3.393852) (5.482797, 3.393652) (5.478567, 3.39325) (5.472228, 3.392635) (5.463785, 3.391792) (5.45325, 3.390699) (5.442733, 3.389569) (5.432234, 3.3884) (5.421753, 3.387192) (5.411291, 3.385946) (5.400847, 3.38466) (5.390421, 3.383336) (5.380015, 3.381972) (5.369627, 3.380569) (5.35926, 3.379126) (5.348911, 3.377644) (5.338583, 3.376121) (5.328274, 3.374558) (5.317985, 3.372955) (5.307717, 3.371311) (5.29747, 3.369627) (5.287243, 3.367901) (5.277038, 3.366134) (5.266853, 3.364326) (5.256691, 3.362476) (5.24655, 3.360583) (5.236431, 3.358649) (5.226335, 3.356672) (5.216261, 3.354653) (5.20621, 3.35259) (5.196182, 3.350483) (5.186178, 3.348333) (5.176198, 3.346139) (5.166242, 3.3439) (5.156311, 3.341616) (5.146404, 3.339287) (5.136522, 3.336912) (5.126666, 3.334492) (5.116835, 3.332026) (5.107031, 3.329512) (5.097254, 3.326951) (5.087504, 3.324341) (5.077782, 3.321682) (5.068089, 3.318973) (5.058424, 3.316215) (5.048788, 3.313407) (5.03918, 3.310549) (5.029603, 3.30764) (5.020055, 3.30468) (5.010539, 3.301666) (5.001056, 3.298597) (4.991608, 3.295469) (4.982195, 3.292282) (4.972817, 3.289036) (4.963475, 3.28573) (4.954168, 3.282368) (4.944894, 3.278951) (4.935655, 3.275478) (4.926453, 3.271945) (4.917292, 3.268345) (4.908178, 3.264669) (4.899117, 3.260906) (4.891721, 3.257742) (4.886153, 3.255305) (4.882389, 3.253634) (4.880415, 3.252751) (4.880225, 3.252666) knots -1 -1 -1 -1 -1 -1 -0.98571429 -0.97142857 -0.95714286 -0.94285714 -0.92857143 -0.91428571 -0.9 -0.88571429 -0.87142857 -0.85714286 -0.84285714 -0.82857143 -0.81428571 -0.8 -0.78571429 -0.77142857 -0.75714286 -0.74285714 -0.72857143 -0.71428571 -0.7 -0.68571429 -0.67142857 -0.65714286 -0.64285714 -0.62857143 -0.61428571 -0.6 -0.58571429 -0.57142857 -0.55714286 -0.54285714 -0.52857143 -0.51428571 -0.5 -0.48571429 -0.47142857 -0.45714286 -0.44285714 -0.42857143 -0.41428571 -0.4 -0.38571429 -0.37142857 -0.35714286 -0.34285714 -0.32857143 -0.31428571 -0.3 -0.28571429 -0.27142857 -0.25714286 -0.24285714 -0.22857143 -0.21428571 -0.2 -0.18571429 -0.17142857 -0.15714286 -0.14285714 -0.12857143 -0.1270499 -0.1270499 -0.1270499 -0.1270499 -0.1270499 -0.1270499
  spline S74 degree 3 poles (4.710813, 3.493519) (4.69728, 3.479434) (4.686627, 3.462841) (4.672282, 3.426506) (4.668727, 3.407111) (4.669251, 3.36805) (4.673325, 3.348758) (4.688639, 3.31282) (4.699732, 3.296519) (4.727543, 3.269085) (4.743995, 3.258216) (4.780139, 3.243396) (4.799486, 3.239586) (4.829536, 3.239595) (4.840025, 3.240704) (4.860597, 3.245098) (4.870623, 3.248371) (4.880225, 3.252666) knots 0 0 0 0 0.00585967 0.00585967 0.01171933 0.01171933 0.017579 0.017579 0.02343867 0.02343867 0.02929834 0.02929834 0.035158 0.035158 0.03831344 0.03831344 0.04146887 0.04146887 0.04146887 0.04146887
  spline S75 degree 5 poles (4.710813, 3.493519) (4.710957, 3.493669) (4.712455, 3.495228) (4.7153, 3.498206) (4.719476, 3.502623) (4.724954, 3.508514) (4.731558, 3.51577) (4.738098, 3.523105) (4.744583, 3.53051) (4.751018, 3.537976) (4.75741, 3.545497) (4.76376, 3.55307) (4.770071, 3.560693) (4.776339, 3.568368) (4.782565, 3.576096) (4.788746, 3.583878) (4.794883, 3.591713) (4.800977, 3.5996) (4.80703, 3.607538) (4.813043, 3.615522) (4.819018, 3.623553) (4.824955, 3.631629) (4.830855, 3.639749) (4.836718, 3.647912) (4.842544, 3.65612) (4.848333, 3.66437) (4.854084, 3.672664) (4.8598, 3.681) (4.865479, 3.689378) (4.871124, 3.697796) (4.876733, 3.706254) (4.882308, 3.714751) (4.887849, 3.723288) (4.893355, 3.731863) (4.898827, 3.740476) (4.904266, 3.749127) (4.909671, 3.757815) (4.915043, 3.766541) (4.920382, 3.775303) (4.925688, 3.784101) (4.930961, 3.792935) (4.936202, 3.801804) (4.941411, 3.810709) (4.946587, 3.819648) (4.951731, 3.828621) (4.956844, 3.837629) (4.961925, 3.84667) (4.966974, 3.855745) (4.971992, 3.864853) (4.976978, 3.873994) (4.981934, 3.883168) (4.986858, 3.892374) (4.991751, 3.901612) (4.996614, 3.910882) (5.001445, 3.920184) (5.006246, 3.929517) (5.011017, 3.938881) (5.015757, 3.948276) (5.020466, 3.957701) (5.025146, 3.967157) (5.029795, 3.976643) (5.034414, 3.986159) (5.039002, 3.995704) (5.04265, 4.003365) (5.045371, 4.009123) (5.04718, 4.012968) (5.048083, 4.014892) knots 0.1270499 0.1270499 0.1270499 0.1270499 0.1270499 0.1270499 0.12857143 0.14285714 0.15714286 0.17142857 0.18571429 0.2 0.21428571 0.22857143 0.24285714 0.25714286 0.27142857 0.28571429 0.3 0.31428571 0.32857143 0.34285714 0.35714286 0.37142857 0.38571429 0.4 0.41428571 0.42857143 0.44285714 0.45714286 0.47142857 0.48571429 0.5 0.51428571 0.52857143 0.54285714 0.55714286 0.57142857 0.58571429 0.6 0.61428571 0.62857143 0.64285714 0.65714286 0.67142857 0.68571429 0.7 0.71428571 0.72857143 0.74285714 0.75714286 0.77142857 0.78571429 0.8 0.81428571 0.82857143 0.84285714 0.85714286 0.87142857 0.88571429 0.9 0.91428571 0.92857143 0.94285714 0.95714286 0.97142857 0.98571429 1 1 1 1 1 1
  arc A25 (5.048083, 4.014892) -> (4.902563, 4.191345) centre (0, 0) ccw
  spline S76 degree 5 poles (4.902563, 4.191345) (4.900503, 4.190825) (4.896384, 4.189782) (4.890212, 4.188206) (4.881997, 4.186084) (4.871753, 4.183397) (4.861532, 4.180674) (4.851334, 4.177916) (4.84116, 4.175122) (4.831011, 4.172294) (4.820885, 4.169429) (4.810784, 4.166529) (4.800708, 4.163592) (4.790656, 4.16062) (4.78063, 4.157611) (4.770629, 4.154566) (4.760654, 4.151485) (4.750705, 4.148367) (4.740782, 4.145212) (4.730885, 4.14202) (4.721015, 4.138791) (4.711171, 4.135525) (4.701355, 4.132221) (4.691566, 4.128879) (4.681805, 4.125499) (4.672072, 4.122081) (4.662367, 4.118625) (4.652691, 4.11513) (4.643043, 4.111596) (4.633425, 4.108023) (4.623836, 4.104411) (4.614278, 4.100759) (4.60475, 4.097066) (4.595252, 4.093334) (4.585786, 4.089561) (4.57635, 4.085747) (4.566947, 4.081892) (4.557576, 4.077995) (4.548237, 4.074057) (4.538931, 4.070076) (4.52966, 4.066052) (4.520422, 4.061985) (4.51122, 4.057873) (4.502054, 4.053716) (4.492923, 4.049515) (4.483829, 4.045269) (4.47477, 4.040978) (4.465749, 4.036641) (4.456765, 4.032258) (4.447821, 4.027827) (4.438918, 4.023346) (4.430057, 4.018813) (4.421241, 4.014227) (4.412469, 4.009586) (4.403741, 4.004894) (4.395056, 4.00015) (4.386413, 3.995358) (4.377812, 3.990515) (4.369257, 3.985619) (4.360753, 3.980663) (4.352307, 3.975638) (4.343927, 3.970537) (4.3371, 3.96628) (4.331969, 3.963022) (4.328504, 3.960796) (4.326688, 3.959622) (4.326513, 3.959509) knots -1 -1 -1 -1 -1 -1 -0.98571429 -0.97142857 -0.95714286 -0.94285714 -0.92857143 -0.91428571 -0.9 -0.88571429 -0.87142857 -0.85714286 -0.84285714 -0.82857143 -0.81428571 -0.8 -0.78571429 -0.77142857 -0.75714286 -0.74285714 -0.72857143 -0.71428571 -0.7 -0.68571429 -0.67142857 -0.65714286 -0.64285714 -0.62857143 -0.61428571 -0.6 -0.58571429 -0.57142857 -0.55714286 -0.54285714 -0.52857143 -0.51428571 -0.5 -0.48571429 -0.47142857 -0.45714286 -0.44285714 -0.42857143 -0.41428571 -0.4 -0.38571429 -0.37142857 -0.35714286 -0.34285714 -0.32857143 -0.31428571 -0.3 -0.28571429 -0.27142857 -0.25714286 -0.24285714 -0.22857143 -0.21428571 -0.2 -0.18571429 -0.17142857 -0.15714286 -0.14285714 -0.12857143 -0.1270499 -0.1270499 -0.1270499 -0.1270499 -0.1270499 -0.1270499
  spline S77 degree 3 poles (4.122321, 4.171678) (4.111097, 4.155693) (4.103102, 4.137669) (4.094471, 4.099569) (4.093918, 4.079859) (4.100399, 4.041336) (4.10737, 4.022891) (4.12799, 3.989712) (4.141442, 3.975295) (4.173115, 3.952429) (4.191033, 3.944199) (4.229016, 3.935069) (4.248717, 3.934257) (4.278414, 3.938853) (4.28861, 3.94155) (4.308271, 3.949034) (4.31768, 3.953799) (4.326513, 3.959509) knots 0 0 0 0 0.00585967 0.00585967 0.01171933 0.01171933 0.017579 0.017579 0.02343867 0.02343867 0.02929834 0.02929834 0.035158 0.035158 0.03831344 0.03831344 0.04146887 0.04146887 0.04146887 0.04146887
  spline S78 degree 5 poles (4.122321, 4.171678) (4.12244, 4.171849) (4.123683, 4.173619) (4.12604, 4.176996) (4.129493, 4.181998) (4.134007, 4.188657) (4.139426, 4.196836) (4.14477, 4.205083) (4.150049, 4.213391) (4.155269, 4.221752) (4.160437, 4.230161) (4.165558, 4.238614) (4.17063, 4.247111) (4.175654, 4.255653) (4.180626, 4.264241) (4.185547, 4.272875) (4.190416, 4.281555) (4.195235, 4.29028) (4.200006, 4.299048) (4.204729, 4.307858) (4.209408, 4.316706) (4.214043, 4.325594) (4.218635, 4.334519) (4.223183, 4.343482) (4.227687, 4.352482) (4.232149, 4.36152) (4.236567, 4.370595) (4.240943, 4.379705) (4.245277, 4.388852) (4.24957, 4.398033) (4.253823, 4.407248) (4.258035, 4.416497) (4.262208, 4.425779) (4.266341, 4.435094) (4.270434, 4.444442) (4.274489, 4.453821) (4.278504, 4.463233) (4.282481, 4.472676) (4.28642, 4.482151) (4.290321, 4.491656) (4.294184, 4.501191) (4.298009, 4.510756) (4.301797, 4.520351) (4.305549, 4.529976) (4.309263, 4.53963) (4.312941, 4.549312) (4.316582, 4.559023) (4.320186, 4.568762) (4.323755, 4.57853) (4.327288, 4.588325) (4.330785, 4.598147) (4.334246, 4.607997) (4.337672, 4.617874) (4.341062, 4.627778) (4.344417, 4.637708) (4.347737, 4.647664) (4.351022, 4.657647) (4.354273, 4.667655) (4.357488, 4.677689) (4.360669, 4.687748) (4.363816, 4.697833) (4.366928, 4.707942) (4.370006, 4.718077) (4.372441, 4.726204) (4.374252, 4.73231) (4.375452, 4.736386) (4.376051, 4.738426) knots 0.1270499 0.1270499 0.1270499 0.1270499 0.1270499 0.1270499 0.12857143 0.14285714 0.15714286 0.17142857 0.18571429 0.2 0.21428571 0.22857143 0.24285714 0.25714286 0.27142857 0.28571429 0.3 0.31428571 0.32857143 0.34285714 0.35714286 0.37142857 0.38571429 0.4 0.41428571 0.42857143 0.44285714 0.45714286 0.47142857 0.48571429 0.5 0.51428571 0.52857143 0.54285714 0.55714286 0.57142857 0.58571429 0.6 0.61428571 0.62857143 0.64285714 0.65714286 0.67142857 0.68571429 0.7 0.71428571 0.72857143 0.74285714 0.75714286 0.77142857 0.78571429 0.8 0.81428571 0.82857143 0.84285714 0.85714286 0.87142857 0.88571429 0.9 0.91428571 0.92857143 0.94285714 0.95714286 0.97142857 0.98571429 1 1 1 1 1 1
  arc A26 (4.376051, 4.738426) -> (4.205301, 4.890597) centre (0, 0) ccw
  spline S79 degree 5 poles (4.205301, 4.890597) (4.203344, 4.889769) (4.199433, 4.888109) (4.193574, 4.885609) (4.18578, 4.882258) (4.176065, 4.878038) (4.16638, 4.873787) (4.156723, 4.869505) (4.147094, 4.865191) (4.137496, 4.860846) (4.127926, 4.85647) (4.118386, 4.852061) (4.108876, 4.847621) (4.099396, 4.843149) (4.089947, 4.838646) (4.080528, 4.83411) (4.07114, 4.829542) (4.061783, 4.824942) (4.052458, 4.820309) (4.043164, 4.815644) (4.033903, 4.810946) (4.024673, 4.806215) (4.015477, 4.801451) (4.006313, 4.796654) (3.997182, 4.791824) (3.988084, 4.78696) (3.979021, 4.782063) (3.969991, 4.777132) (3.960997, 4.772167) (3.952036, 4.767168) (3.943112, 4.762134) (3.934223, 4.757066) (3.92537, 4.751962) (3.916553, 4.746824) (3.907774, 4.74165) (3.899031, 4.73644) (3.890326, 4.731195) (3.88166, 4.725914) (3.873032, 4.720596) (3.864443, 4.715241) (3.855894, 4.709849) (3.847386, 4.704419) (3.838919, 4.698951) (3.830495, 4.693444) (3.822113, 4.687898) (3.813773, 4.682313) (3.805476, 4.67669) (3.797222, 4.671027) (3.789013, 4.665324) (3.780849, 4.65958) (3.772735, 4.653792) (3.76467, 4.647959) (3.756657, 4.642081) (3.748696, 4.636156) (3.740787, 4.630186) (3.732928, 4.624172) (3.725117, 4.618116) (3.717357, 4.612017) (3.709649, 4.605873) (3.702001, 4.599677) (3.694422, 4.593422) (3.686918, 4.587101) (3.680822, 4.581853) (3.676248, 4.577849) (3.673164, 4.57512) (3.671548, 4.573683) (3.671392, 4.573544) knots -1 -1 -1 -1 -1 -1 -0.98571429 -0.97142857 -0.95714286 -0.94285714 -0.92857143 -0.91428571 -0.9 -0.88571429 -0.87142857 -0.85714286 -0.84285714 -0.82857143 -0.81428571 -0.8 -0.78571429 -0.77142857 -0.75714286 -0.74285714 -0.72857143 -0.71428571 -0.7 -0.68571429 -0.67142857 -0.65714286 -0.64285714 -0.62857143 -0.61428571 -0.6 -0.58571429 -0.57142857 -0.55714286 -0.54285714 -0.52857143 -0.51428571 -0.5 -0.48571429 -0.47142857 -0.45714286 -0.44285714 -0.42857143 -0.41428571 -0.4 -0.38571429 -0.37142857 -0.35714286 -0.34285714 -0.32857143 -0.31428571 -0.3 -0.28571429 -0.27142857 -0.25714286 -0.24285714 -0.22857143 -0.21428571 -0.2 -0.18571429 -0.17142857 -0.15714286 -0.14285714 -0.12857143 -0.1270499 -0.1270499 -0.1270499 -0.1270499 -0.1270499 -0.1270499